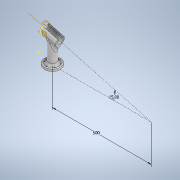
# Autodesk Inventor part: Suport_torta_nle
Saved by Autodesk Inventor 2022.6 (Build 266554000, 554)
## iProperties
Created: 2026-06-15
Part Number: Suport_torta_nle
Material: Generic
Document SubType Name: Modeling
Designer: Dragos Macovei
Density: 1 g/cm^3
Appearance: Default
Author: Dragos Macovei
Autodesk Inventor part; units mm, degrees
ref_plane "YZ Plane" through (0, 0, 0) normal (1, 0, 0) x (0, 1, 0)
ref_plane "XZ Plane" through (0, 0, 0) normal (0, 1, 0) x (-1, 0, 0)
ref_plane "XY Plane" through (0, 0, 0) normal (0, 0, 1) x (1, 0, 0)
sketch "Sketch1" plane through (0, 0, 0) normal (0, 1, 0) x (-1, 0, 0)
  line L0 (15.5703, 0) -> (-15.0013, 0) construction
  point P0 (0, 0)
  constraints: 2 end point, 1 horizontal
sketch "Sketch2" plane through (0, 0, 0) normal (0, 1, 0) x (-1, 0, 0)
  circle A0 centre (0, 0) radius 20
  dimension "d1" = 40
  constraints: 1 centre point
  measures "d1" diameter of A0
extrude "Extrusion1" add sketch "Sketch2" along normal blind 130
sketch "Sketch3" plane through (0, 0, 0) normal (0, 0, 1) x (1, 0, 0)
  line L0 (500, 0) -> (-52.0719, 147.9272) construction
  line L1 (0, 0) -> (500, 0) construction
  line L2 (20, 0) -> (-20, 0) construction
  dimension "d4" = 15
  dimension "d16" = 500
  constraints: 4 end point, 1 collinear
  measures "d4" angle of L0 L1
  measures "d16" distance of L1.start L0.start
sketch "Sketch4" plane through (0, 0, 0) normal (0, 0, 1) x (1, 0, 0)
  line L0 (500, 0) -> (-52.0719, 147.9272) construction
  line L1 (-38.637, 144.3274) -> (-32.8136, 166.0607)
  line L2 (-32.8136, 166.0607) -> (44.4605, 145.3552)
  line L3 (44.4605, 145.3552) -> (38.637, 123.6218)
  line L4 (-38.637, 144.3274) -> (38.637, 123.6218)
  line L5 (20, 130) -> (-20, 130) projected
  line L6 (20, 0) -> (-20, 0) projected
  line L7 (20, 130) -> (-20, 130) projected
  point P0 (0, 0)
  point P1 (0, 130)
  point P2 (0, 133.9746)
  point P3 (0, 130)
  dimension "d5" = 22.5
  dimension "d6" = 80
  dimension "d17" = 3.9746
  constraints: 8 end point, 3 midpoint, 3 perpendicular, 3 point on line, 1 collinear
  measures "d5" distance of L1.start L1.end
  measures "d6" distance of L1.end L2.end
  measures "d17" distance of point (0, 130) point (0, 133.975)
revolve "Revolution1" add sketch "Sketch4" angle 360 about axis through (500, 0, 0) along (-0.9659258, 0.258819, 0)
sketch "Sketch5" plane through (-38.637, 144.3274, 0) normal (-0.9659258, 0.258819, 0) x (0, 0, 1)
  circle A0 centre (0, 0) radius 22.5 projected
  circle A1 centre (0, 0) radius 16
  point P0 (0, -129.4095)
  dimension "d8" = 32
  constraints: 1 centre point, 1 coincident
  measures "d8" diameter of A1
extrude "Extrusion2" cut sketch "Sketch5" against normal blind 130 contours A1
sketch "Sketch6" plane through (-38.637, 144.3274, 0) normal (-0.9659258, 0.258819, 0) x (0, 0, 1)
  circle A0 centre (0, 0) radius 22.5 projected
  point P0 (0, -129.4095)
  point P1 (0, 22.5)
  constraints: 1 vertical alignment, 1 other
ref_plane "Work Plane1" through (-32.8136, 166.0607, 0) normal (0.258819, 0.9659258, 0) x (-0.9659258, 0.258819, 0)
sketch "Sketch7" plane through (-32.8136, 166.0607, 0) normal (0.258819, 0.9659258, 0) x (-0.9659258, 0.258819, 0)
  line L0 (0, 16) -> (0, -16) projected
  line L1 (-80, -16) -> (-80, 16) projected
  line L2 (0, -16) -> (-80, -16) projected
  line L3 (0, 16) -> (-80, 16) projected
  line L4 (0, 22.5) -> (0, -22.5) projected
  line L5 (0, 0) -> (0, -13.125)
  line L6 (0, -13.125) -> (0, 13.125)
  line L7 (0, 13.125) -> (-80, 13.125)
  line L8 (-80, 22.5) -> (-80, -22.5) projected
  line L9 (0, -13.125) -> (-80, -13.125)
  line L10 (-80, 13.125) -> (-80, -13.125)
  point P0 (-74.6752, 0)
  point P1 (-50, -4.9511)
  point P2 (-50, 4.9511)
  dimension "d12" = 13.125
  dimension "d13" = 26.25
  constraints: 10 end point, 2 perpendicular, 1 horizontal, 8 other
  measures "d12" distance of L5.start L5.end
  measures "d13" distance of L5.end L6.end
extrude "Extrusion3" cut sketch "Sketch7" against normal blind 15.25 contours L0 L9 L1 L7
sketch "Sketch8" plane through (0, 0, 0) normal (0, -1, 0) x (1, 0, 0)
  circle A0 centre (0, 0) radius 20 projected
  circle A1 centre (0, 0) radius 40
  dimension "d19" = 80
  constraints: 1 centre point, 1 coincident
  measures "d19" diameter of A1
extrude "Extrusion4" add sketch "Sketch8" against normal blind 10
sketch "Sketch9" plane through (0, 10, 0) normal (0, 1, 0) x (1, 0, 0)
  circle A0 centre (0, 0) radius 40 projected
  circle A1 centre (0, 0) radius 20 projected
  circle A2 centre (0, 0) radius 40 projected
  circle A3 centre (0, 0) radius 40 projected
  line L0 (0, -40) -> (0, -20)
  circle A4 centre (0, 0) radius 30
  circle A5 centre (0, -30) radius 2
  dimension "d23" = 10
  dimension "d24" = 4
  constraints: 3 vertical alignment, 2 coincident, 2 end point, 1 centre point, 1 midpoint, 1 vertical, 4 other
  measures "d23" distance of L0.start point (0, -30)
  measures "d24" diameter of A5
extrude "Extrusion5" cut sketch "Sketch9" against normal through all contours A5 A4 L0 | L0 A4 A5 | A4 A5 L0 | L0 A5 A4
pattern_circular "Circular Pattern1" count 6 over 360 about axis through (0, 0, 0) along (0, 1, 0) of "Extrusion5"
fillet "Fillet1" radius 30 1 edges at (19.9997, 105.3223, -0.1176)
fillet "Fillet2" radius 11 1 edges at (20, 10, 0)
fillet "Fillet3" radius 1 18 edges at (0, 10, 32) (1.9393, 10.0092, 30.4892) (-0.4918, 10.3986, 28.0614) (-27.7128, 10, 16) (-25.4348, 10.0092, 16.924) (-24.5478, 10.3986, 13.6048) (-27.374, 10.0092, -13.5651) (-24.056, 10.3986, -14.4566) (-27.7128, 10, -16) (27.7128, 10, 16) (27.374, 10.0092, 13.5651) (24.056, 10.3986, 14.4566) (27.7128, 10, -16) (25.4348, 10.0092, -16.924) (24.5478, 10.3986, -13.6048) (-1.9393, 10.0092, -30.4892) (0.4918, 10.3986, -28.0614) (0, 10, -32)
sketch "Sketch10" plane through (-38.637, 144.3274, 0) normal (-0.9659258, 0.258819, 0) x (0, 0, 1)
  arc A0 (-13.125, 18.2752) -> (13.125, 18.2752) centre (0, 0) ccw projected
  point P0 (0, -129.4095)
  point P1 (22.5, 0)
  constraints: 1 point on circle
ref_plane "Work Plane2" through (-38.637, 144.3274, 22.5) normal (0, 0, 1) x (1, 0, 0)
sketch "Sketch11" plane through (-38.637, 144.3274, 22.5) normal (0, 0, 1) x (1, 0, 0)
  line L0 (82.004, -3.053) -> (73.5153, -34.7333) projected
  line L1 (82.004, -3.053) -> (4.73, 17.6525) projected
  line L2 (4.73, 17.6525) -> (4.73, 17.6525) projected
  line L3 (4.73, 17.6525) -> (82.004, -3.053) projected
  line L4 (73.5153, -34.7333) -> (82.004, -3.053) projected
  line L5 (79.6424, -11.8667) -> (79.6424, -11.8667) projected
  line L6 (2.3684, 8.8388) -> (2.3684, 8.8388) projected
  line L7 (-4.1411, -15.4548) -> (73.133, -36.1603) projected
  line L8 (-5.8234, -21.7333) -> (-3.5984, -22.3295) projected
  line L9 (-5.8234, -21.7333) -> (71.4506, -42.4389)
  circle A0 centre (64.2062, -40.4977) radius 2.5
  circle A1 centre (43.9218, -35.0625) radius 2.5
  circle A2 centre (23.6373, -29.6273) radius 2.5
  circle A3 centre (3.3529, -24.1921) radius 2.5
  line L10 (2.3684, 8.8388) -> (79.6424, -11.8667) projected
  line L11 (79.6424, -11.8667) -> (2.3684, 8.8388) projected
  point P0 (38.637, -144.3274)
  dimension "d33" = 5
  dimension "d34" = 7.5
  dimension "d39" = 21
  constraints: 4 centre point, 3 point on line, 2 end point, 1 collinear, 8 other
  measures "d33" diameter of A0
  measures "d34" distance of L9.end A0.centre
  measures "d39" distance of A0.centre A1.centre
extrude "Extrusion6" cut sketch "Sketch11" against normal through all
fillet "Fillet4" radius 1 4 edges at (4.73, 151.6271, -13.125) (4.73, 151.6271, 13.125) (2.3684, 142.8134, 13.125) (2.3684, 142.8134, -13.125)
fillet "Fillet5" radius 1 4 edges at (-37.1428, 121.8072, -7.3556) (-33.3014, 118.6125, -3.9154) (-33.305, 118.6078, 3.8943) (-37.1412, 121.8089, 7.3609)
body "Solid1"
